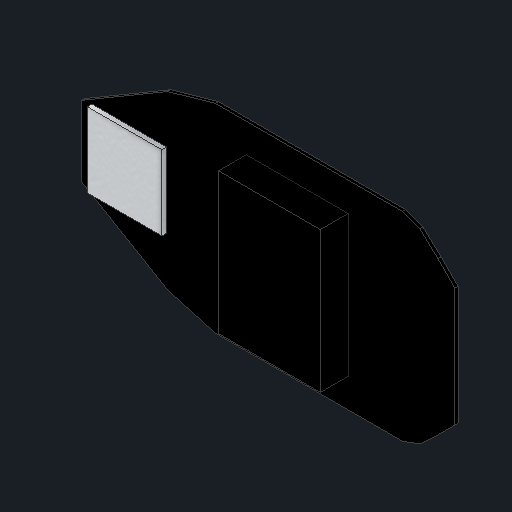
# Autodesk Inventor part: MobileDetect Pouch
Saved by Autodesk Inventor 2027.2 (Build 312334000, 334)
## iProperties
Created: 2026-11-11
Part Number: MobileDetect Pouch
Material: Generic
Description: DetectaChem MobileDetect pouch, measured 95.25 x 50.8 mm, film 0.8 mm, pad 19.05 mm square x 2 mm; ampoule bulge position assumed
Document SubType Name: Modeling
Designer: isaac
Density: 1 g/cm^3
Appearance: Default
Author: isaac
Autodesk Inventor part; units mm, degrees
ref_plane "YZ Plane" through (0, 0, 0) normal (1, 0, 0) x (0, 1, 0)
sketch "Sketch1" plane through (0, 0, 0) normal (0, 0, 1) x (1, 0, 0)
  line L0 (0, -9.03) -> (21.89, -21.92)
  line L1 (21.89, -21.92) -> (34.1, -25.4)
  line L2 (34.1, -25.4) -> (81.9, -25.4)
  line L3 (81.9, -25.4) -> (86.3, -23.8)
  line L4 (86.3, -23.8) -> (90.9, -19.5)
  line L5 (90.9, -19.5) -> (95.25, -15.15)
  line L6 (95.25, -15.15) -> (95.25, 15.15)
  line L7 (95.25, 15.15) -> (90.9, 19.5)
  line L8 (90.9, 19.5) -> (86.3, 23.8)
  line L9 (86.3, 23.8) -> (81.9, 25.4)
  line L10 (81.9, 25.4) -> (34.1, 25.4)
  line L11 (34.1, 25.4) -> (21.89, 21.92)
  line L12 (21.89, 21.92) -> (0, 9.03)
  line L13 (0, 9.03) -> (0, -9.03)
  constraints: 28 end point
extrude "Body" add sketch "Sketch1" along normal blind 0.8
ref_plane "Work Plane1" through (0, 0, 0.8) normal (0, 0, 1) x (1, 0, 0)
sketch "Sketch2" plane through (0, 0, 0.8) normal (0, 0, 1) x (1, 0, 0)
  line L0 (2.62, -9.525) -> (21.67, -9.525)
  line L1 (21.67, -9.525) -> (21.67, 9.525)
  line L2 (21.67, 9.525) -> (2.62, 9.525)
  line L3 (2.62, 9.525) -> (2.62, -9.525)
  constraints: 8 end point, 2 parallel, 1 horizontal, 1 perpendicular
extrude "Pad" add sketch "Sketch2" along normal blind 1.2
ref_plane "Work Plane2" through (0, 0, 0.8) normal (0, 0, 1) x (1, 0, 0)
sketch "Sketch3" plane through (0, 0, 0.8) normal (0, 0, 1) x (1, 0, 0)
  line L0 (42, -18) -> (68, -18)
  line L1 (68, -18) -> (68, 18)
  line L2 (68, 18) -> (42, 18)
  line L3 (42, 18) -> (42, -18)
  constraints: 8 end point, 2 parallel, 1 horizontal, 1 perpendicular
extrude "Ampoules" add sketch "Sketch3" along normal blind 7.1
body "Solid1"
